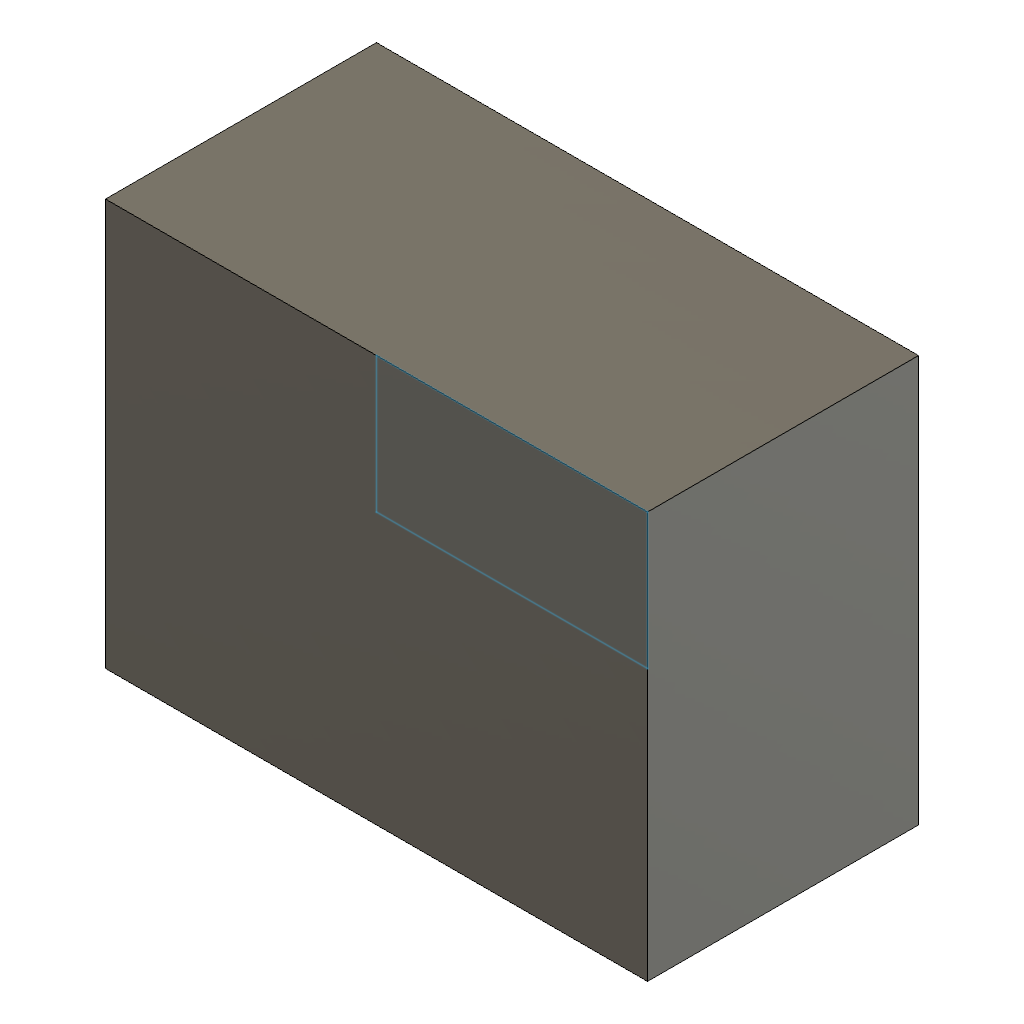
small_profile_extended (Autodesk Fusion 360 design; units mm, degrees)
part number: 2026-10-21-16-22-07-162
Autodesk Fusion 360 part; units mm, degrees
sketch "OwnedProfileSplitBlockSketch_0_small_profile_extended" plane through (0, 0, 0) normal (0, 0, 1) x (1, 0, 0)
  line L0 (0, 0) -> (40, 0)
  line L1 (40, 0) -> (40, 30)
  line L2 (40, 30) -> (0, 30)
  line L3 (0, 30) -> (0, 0)
extrude "OwnedProfileSplitBlockExtrude_0_small_profile_extended" add sketch "OwnedProfileSplitBlockSketch_0_small_profile_extended" along normal blind 20
ref_plane "WorkPlane1" through (0, 0, 10) normal (0, 0, 1) x (1, 0, 0)
sketch "OwnedSplitProfileBoundary_small_profile_extended" plane through (0, 0, 10) normal (0, 0, 1) x (1, 0, 0)
  line L0 (10, 10) -> (30, 10)
  line L1 (30, 10) -> (30, 20)
  line L2 (30, 20) -> (10, 20)
  line L3 (10, 20) -> (10, 10)
named bodies: "OwnedProfileSplitBlock_0_small_profile_extended"
